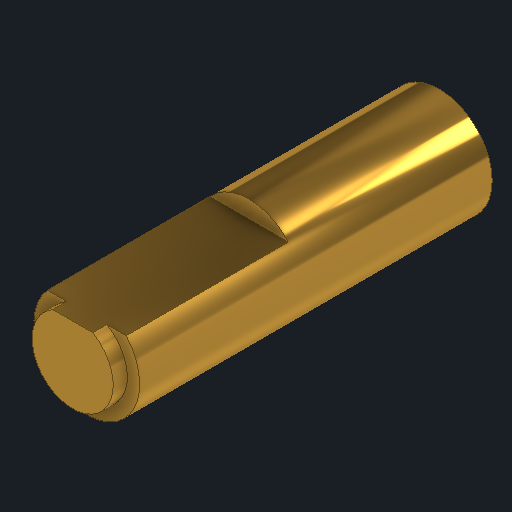
# Autodesk Inventor part: worm_shaft_6mm
Saved by Autodesk Inventor 2027.1 (Build 311270010, 270A)
## iProperties
Created: 2026-11-03
Part Number: worm_shaft_6mm
Material: Generic
Description: Worm shaft end, 6 mm (measured) with a D-flat (photos 08/20; flat depth estimated); motor coupling point
Document SubType Name: Modeling
Designer: Claude (from photos)
Density: 1 g/cm^3
Appearance: Brass - Polished
Author: alexg
Autodesk Inventor part; units mm, degrees
ref_plane "YZ Plane" through (0, 0, 0) normal (1, 0, 0) x (0, 1, 0)
sketch "Worm shaft 6mm sketch" plane through (0, 0, 0) normal (0, 0, 1) x (1, 0, 0)
  circle A0 centre (0, 0) radius 3
  constraints: 1 centre point
extrude "Worm shaft 6mm" add sketch "Worm shaft 6mm sketch" along normal blind 20
ref_plane "Work Plane1" through (0, 0, 20) normal (0, 0, 1) x (1, 0, 0)
sketch "Chamfered tip sketch" plane through (0, 0, 20) normal (0, 0, 1) x (1, 0, 0)
  circle A0 centre (0, 0) radius 2.3
  constraints: 1 centre point
extrude "Chamfered tip" add sketch "Chamfered tip sketch" along normal blind 0.8
ref_plane "Work Plane2" through (0, 2, 0) normal (0, 1, 0) x (-1, 0, 0)
sketch "D flat (5.0 across) sketch" plane through (0, 2, 0) normal (0, 1, 0) x (-1, 0, 0)
  line L0 (4, 10.8) -> (-4, 10.8)
  line L1 (-4, 10.8) -> (-4, 21)
  line L2 (-4, 21) -> (4, 21)
  line L3 (4, 21) -> (4, 10.8)
  constraints: 8 end point, 2 parallel, 1 horizontal, 1 perpendicular
extrude "D flat (5.0 across)" cut sketch "D flat (5.0 across) sketch" along normal blind 2
body "Solid1"
